Autodesk Fusion 360 part; units mm, degrees
(part 2 of 2)
sketch "Boceto39" plane through (0, 14.8166, 5.3928) normal (0, -0.939693, -0.34202) x (1, 0, 0) in component "Techo solar"
  line L0 (-57.5, 109.9365) -> (-55, 109.9365)
  line L1 (-55, 109.9365) -> (-55, 110.1365)
  line L2 (-55, 110.1365) -> (-54, 110.1365)
  line L3 (-54, 110.1365) -> (-54, 111.3365)
  line L4 (-54, 111.3365) -> (-57.5, 111.3365)
  line L5 (-57.5, 111.3365) -> (-57.5, 109.9365)
extrude "Riel panel izquierdo (1)" add sketch "Boceto39" against normal blind 110.25 bodies 5 in component "Techo solar"
sketch "Boceto40" plane through (0, 0, 0) normal (0, 0, 1) x (1, 0, 0) in component "Techo solar"
  point P0 (0, -21.4158)
  point P1 (10, -21.4158)
  point P2 (0, -24.836)
ref_plane "PlanoDeObra31" through (0, -21.4158, 104.9406) normal (0, -0.939693, -0.34202) x (1, 0, 0) in component "Techo solar"
sketch "Boceto41" plane through (0, 14.8166, 5.3928) normal (0, -0.939693, -0.34202) x (1, 0, 0) in component "Techo solar"
  line L0 (28, 109.9365) -> (25.6, 109.9365)
  line L1 (25.6, 109.9365) -> (25.6, 110.1365)
  line L2 (25.6, 110.1365) -> (24.6, 110.1365)
  line L3 (24.6, 110.1365) -> (24.6, 111.3365)
  line L4 (24.6, 111.3365) -> (28, 111.3365)
  line L5 (28, 111.3365) -> (28, 109.9365)
extrude "Riel panel derecho (1)" add sketch "Boceto41" against normal blind 110.25 bodies 5 in component "Techo solar"
ref_plane "PlanoDeObra32" through (24, 0, 0) normal (1, 0, 0) x (0, 1, 0) in component "Techo solar"
sketch "Boceto43" plane through (0, 0, 0) normal (0, 0, 1) x (1, 0, 0) in component "Techo solar"
  point P0 (0, -22.8029)
  point P1 (10, -22.8029)
  point P2 (0, -13.406)
ref_plane "PlanoDeObra33" through (0, -22.8029, 100.7111) normal (0, -0.34202, 0.939693) x (1, 0, 0) in component "Techo solar"
sketch "Boceto45" plane through (0, 0, 0) normal (0, 0, 1) x (1, 0, 0) in component "Techo solar"
  point P0 (0, -23.2476)
  point P1 (10, -23.2476)
  point P2 (0, -13.8506)
ref_plane "PlanoDeObra34" through (0, -23.2476, 101.9327) normal (0, -0.34202, 0.939693) x (1, 0, 0) in component "Techo solar"
sketch "Boceto47" plane through (0, 0, 0) normal (0, 0, 1) x (1, 0, 0) in component "Techo solar"
  point P0 (0, -25.351)
  point P1 (10, -25.351)
  point P2 (0, -15.9541)
ref_plane "PlanoDeObra35" through (0, -25.351, 107.7118) normal (0, -0.34202, 0.939693) x (1, 0, 0) in component "Techo solar"
sketch "Boceto48" plane through (0, -37.5834, 103.2595) normal (0, -0.34202, 0.939693) x (1, 0, 0) in component "Techo solar"
  line L0 (-41, 15.7675) -> (11, 15.7675)
  line L1 (11, 15.7675) -> (11, 20.0175)
  line L2 (11, 20.0175) -> (-41, 20.0175)
  line L3 (-41, 20.0175) -> (-41, 15.7675)
extrude "Quitar pestanas delanteras (1)" cut sketch "Boceto48" along normal blind 2.05 bodies 5 in component "Techo solar"
ref_plane "PlanoDeObra36" through (-57.5, 0, 0) normal (1, 0, 0) x (0, 1, 0) in component "Techo solar"
sketch "Boceto49" plane through (-57.5, 0, 0) normal (1, 0, 0) x (0, 0, -1) in component "Techo solar"
  line L0 (-108.6993, -22.7839) -> (-109.3663, -20.9515)
  line L1 (-109.3663, -20.9515) -> (-109.5542, -21.0199)
  line L2 (-109.5542, -21.0199) -> (-109.8962, -20.0802)
  line L3 (-109.8962, -20.0802) -> (-111.0239, -20.4907)
  line L4 (-111.0239, -20.4907) -> (-110.0149, -23.2628)
  line L5 (-110.0149, -23.2628) -> (-108.6993, -22.7839)
extrude "Tope delantero panel (1)" add sketch "Boceto49" along normal blind 85.5 bodies 5 in component "Techo solar"
ref_plane "PlanoDeObra35" through (0, 0, 96) normal (0, 0, 1) x (1, 0, 0) in component "Cuerpo"
sketch "Boceto40 (2)" plane through (0, 0, 96) normal (0, 0, 1) x (1, 0, 0) in component "Cuerpo"
  line L0 (-33.9, 36.9) -> (-28.1, 36.9)
  line L1 (-28.1, 36.9) -> (-28.1, 62.5)
  line L2 (-28.1, 62.5) -> (-33.9, 62.5)
  line L3 (-33.9, 62.5) -> (-33.9, 36.9)
  line L4 (29.1, 36.9) -> (34.9, 36.9)
  line L5 (34.9, 36.9) -> (34.9, 62.5)
  line L6 (34.9, 62.5) -> (29.1, 62.5)
  line L7 (29.1, 62.5) -> (29.1, 36.9)
extrude "Union postes LiPo al techo (1)" add sketch "Boceto40 (2)" along normal blind 1.6 bodies 1 in component "Cuerpo"
sketch "Boceto50" plane through (0, 0, 0) normal (0, 0, 1) x (1, 0, 0) in component "Techo solar"
  point P0 (0, -24)
  point P1 (10, -24)
  point P2 (0, -14.6031)
ref_plane "PlanoDeObra37" through (0, -24, 104) normal (0, -0.34202, 0.939693) x (1, 0, 0) in component "Techo solar"
sketch "Boceto51" plane through (0, -36.2324, 99.5478) normal (0, -0.34202, 0.939693) x (1, 0, 0) in component "Techo solar"
  line L0 (-55, 19.7175) -> (-39, 19.7175)
  line L1 (-39, 19.7175) -> (-39, 116.3175)
  line L2 (-39, 116.3175) -> (-55, 116.3175)
  line L3 (-55, 116.3175) -> (-55, 19.7175)
extrude "Piso franja izquierda panel (1)" add sketch "Boceto51" along normal blind 1.4 bodies 5 in component "Techo solar"
sketch "Boceto52" plane through (0, 0, 0) normal (0, 0, 1) x (1, 0, 0) in component "Techo solar"
  point P0 (0, -22.8029)
  point P1 (10, -22.8029)
  point P2 (0, -13.406)
ref_plane "PlanoDeObra38" through (0, -22.8029, 100.7111) normal (0, -0.34202, 0.939693) x (1, 0, 0) in component "Techo solar"
ref_plane "PlanoDeObra36" through (0, 35.9, 0) normal (0, 1, 0) x (0, 0, 1) in component "Cuerpo"
sketch "Boceto41 (2)" plane through (0, 35.9, 0) normal (0, 1, 0) x (1, 0, 0) in component "Cuerpo"
  circle A0 centre (-18, -10.5) radius 1.75
  circle A1 centre (33, -10.5) radius 1.75
  circle A2 centre (-18, -33.5) radius 1.75
  circle A3 centre (33, -33.5) radius 1.75
extrude "Insertos ESP32 M2.5 (1)" cut sketch "Boceto41 (2)" along normal blind 5 bodies 1 in component "Cuerpo"
ref_plane "PlanoDeObra37" through (0, 40.9, 0) normal (0, 1, 0) x (0, 0, 1) in component "Cuerpo"
sketch "Boceto42" plane through (0, 40.9, 0) normal (0, 1, 0) x (1, 0, 0) in component "Cuerpo"
  circle A0 centre (-18, -10.5) radius 1.35
  circle A1 centre (33, -10.5) radius 1.35
  circle A2 centre (-18, -33.5) radius 1.35
  circle A3 centre (33, -33.5) radius 1.35
extrude "Insertos ESP32 (paso M2.5) (1)" cut sketch "Boceto42" along normal blind 4 bodies 1 in component "Cuerpo"
ref_plane "PlanoDeObra21" through (0, 6.5, 0) normal (0, 1, 0) x (0, 0, 1) in component "Tapa frontal"
sketch "Boceto21 (3)" plane through (0, 6.5, 0) normal (0, 1, 0) x (1, 0, 0) in component "Tapa frontal"
  circle A0 centre (-7.75, -38.5) radius 1.75
  circle A1 centre (7.75, -38.5) radius 1.75
extrude "Insertos semaforo M2.5 (1)" cut sketch "Boceto21 (3)" against normal blind 5 bodies 2 in component "Tapa frontal"
ref_plane "PlanoDeObra22" through (0, 1.5, 0) normal (0, 1, 0) x (0, 0, 1) in component "Tapa frontal"
sketch "Boceto22 (3)" plane through (0, 1.5, 0) normal (0, 1, 0) x (1, 0, 0) in component "Tapa frontal"
  circle A0 centre (-7.75, -38.5) radius 1.35
  circle A1 centre (7.75, -38.5) radius 1.35
extrude "Insertos semaforo (paso M2.5) (1)" cut sketch "Boceto22 (3)" against normal blind 2 bodies 2 in component "Tapa frontal"
component "Cuerpo" placed x (1, 0, 0) y (0, 1, 0) z (0, 0, 1) at (0, 0, 0)
component "Tapa frontal" placed x (1, 0, 0) y (0, 1, 0) z (0, 0, 1) at (0, 0, 0)
component "Junta TPU" placed x (1, 0, 0) y (0, 1, 0) z (0, 0, 1) at (0, 0, 0)
component "Techo solar" placed x (1, 0, 0) y (0, 1, 0) z (0, 0, 1) at (0, 0, 0)
component "Tapa sensor" placed x (1, 0, 0) y (0, 1, 0) z (0, 0, 1) at (0, 0, 0)
component "Soporte pared" placed x (1, 0, 0) y (0, 1, 0) z (0, 0, 1) at (0, 0, 0)
component "Pared (referencia)" placed x (1, 0, 0) y (0, 1, 0) z (0, 0, 1) at (0, 0, 0)
component "Traba bateria" placed x (1, 0, 0) y (0, 1, 0) z (0, 0, 1) at (0, 0, 0)
equation "ancho = 110 mm" comment "Ancho exterior (X)"
equation "alto = 100 mm" comment "Alto exterior (Z)"
equation "fondo = 65 mm" comment "Fondo sin tapa (Y)"
equation "pared = 2.5 mm" comment "Grosor de pared"
equation "r_esq = 8 mm" comment "Redondeo esquinas verticales"
equation "r_borde = 3 mm" comment "Redondeo aristas"
equation "incl_techo = 20 deg" comment "Inclinacion del panel"
equation "d8 = alto"
equation "d11 = r_esq"
equation "d13 = r_borde"
equation "d18 = pared"
equation "d138 = -( 40 mm )"
equation "d164 = -( 2.6 mm )"
equation "d166 = -( 4.6 mm )"
equation "d182 = -( 2.5 mm )"
equation "d381 = -( 26.10 mm )"
equation "d385 = -( 27.10 mm )"
equation "d393 = -( 7.00 mm )"
equation "d397 = -( 7.00 mm )"
equation "d484 = -( 5.00 mm )"
equation "d488 = -( 3.00 mm )"
equation "d540 = -( 110.25 mm )"
equation "d543 = -( 110.25 mm )"
equation "d597 = -( 5.00 mm )"
equation "d601 = -( 2.00 mm )"
named bodies: "Cuerpo", "Tapa", "Frente semaforo", "Junta", "Techo", "Tapa sensor", "Soporte pared", "Pared", "Traba bateria"
